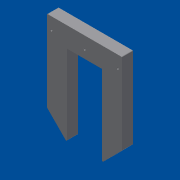
# Autodesk Inventor part: Foam v5
Saved by Autodesk Inventor 2019 (Build 230136000, 136)
## iProperties
Created: 2019-04-15
Part Number: Foam v5
Material: Generic
Document SubType Name: Modeling
Designer: --------
Density: 1 g/cm^3
Appearance: Default
Author: --------
Autodesk Inventor part; units mm, degrees
ref_plane "YZ Plane" through (0, 0, 0) normal (1, 0, 0) x (0, 1, 0)
ref_plane "XZ Plane" through (0, 0, 0) normal (0, 1, 0) x (-1, 0, 0)
ref_plane "XY Plane" through (0, 0, 0) normal (0, 0, 1) x (1, 0, 0)
sketch "Sketch3" plane through (0, 0, 0) normal (0, 0, 1) x (1, 0, 0)
  line L0 (0, 0) -> (185, 0)
  line L1 (185, 0) -> (185, -250)
  line L2 (185, -250) -> (0, -250)
  line L3 (0, -250) -> (0, 0)
  line L4 (92.5, -250) -> (135.5, -250)
  line L5 (185, 0) -> (185, -200)
  line L6 (185, -200) -> (135.5, -250)
  line L7 (92.5, -250) -> (49.5, -250)
  line L8 (0, 0) -> (0, -200)
  line L9 (0, -200) -> (49.5, -250)
  line L10 (49.5, -250) -> (49.5, -50)
  line L11 (49.5, -50) -> (135.5, -50)
  line L12 (135.5, -50) -> (135.5, -250)
  dimension "d7" = 185
  dimension "d8" = 250
  dimension "d9" = 43
  dimension "d10" = 200
  dimension "d11" = 43
  dimension "d12" = 200
  dimension "d13" = 200
  constraints: 26 end point, 5 perpendicular, 4 point on line, 1 horizontal, 1 midpoint, 1 vertical
  measures "d7" distance of L0.start L0.end
  measures "d8" distance of L0.end L1.end
  measures "d9" distance of L4.start L4.end
  measures "d10" distance of L0.end L5.end
  measures "d11" distance of L4.start L7.end
  measures "d12" distance of L0.start L8.end
  measures "d13" distance of L7.end L10.end
extrude "Extrusion2" add sketch "Sketch3" along normal blind 27.5 contours L0 L1 L6 L12 L11 L10 L9 L3
fillet "Fillet1" radius 2 6 edges at (185, 0, 13.75) (0, 0, 13.75) (49.5, -250, 13.75) (135.5, -250, 13.75) (185, -200, 13.75) (0, -200, 13.75)
sketch "Sketch4" plane through (0, 0, 27.5) normal (0, 0, 1) x (1, 0, 0)
  arc A0 (0, -199.1775) -> (0.5787, -200.5845) centre (2, -199.1775) ccw projected
  line L0 (0.5787, -200.5845) -> (46.0787, -246.5441) projected
  arc A1 (46.0787, -246.5441) -> (49.5, -245.137) centre (47.5, -245.137) ccw projected
  line L1 (49.5, -245.137) -> (49.5, -50) projected
  line L2 (49.5, -50) -> (135.5, -50) projected
  line L3 (135.5, -50) -> (135.5, -245.137) projected
  arc A2 (135.5, -245.137) -> (138.9213, -246.5441) centre (137.5, -245.137) ccw projected
  line L4 (138.9213, -246.5441) -> (184.4213, -200.5845) projected
  arc A3 (184.4213, -200.5845) -> (185, -199.1775) centre (183, -199.1775) ccw projected
  line L5 (185, -199.1775) -> (185, -2) projected
  arc A4 (185, -2) -> (183, 0) centre (183, -2) ccw projected
  line L6 (183, 0) -> (2, 0) projected
  arc A5 (2, 0) -> (0, -2) centre (2, -2) ccw projected
  line L7 (0, -2) -> (0, -199.1775) projected
  line L8 (183, 0) -> (2, 0) projected
  line L9 (92.5, 0) -> (92.5, -30)
  line L10 (185, -199.1775) -> (185, -2) projected
  line L11 (185, -30) -> (174.25, -30)
  line L12 (0, -2) -> (0, -199.1775) projected
  line L13 (0, -30) -> (10.75, -30)
  point P0 (0, 0)
  dimension "d17" = 30
  dimension "d18" = 10.75
  dimension "d19" = 10.75
  constraints: 6 end point, 2 perpendicular, 2 point on line, 1 midpoint, 1 vertical
  measures "d17" distance of L9.start L9.end
  measures "d18" distance of L11.start L11.end
  measures "d19" distance of L13.start L13.end
hole "Hole1" at (10.75, -30, 27.5) at (92.5, -30, 27.5) at (174.25, -30, 27.5) direction (0, 0, -1) diameter 5 end through all
body "Solid2"
